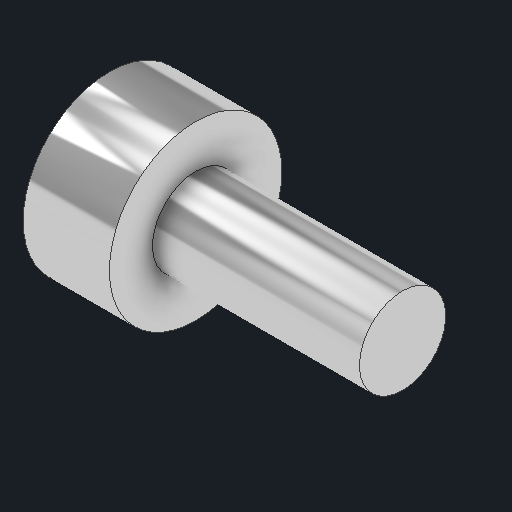
# Autodesk Inventor part: c8n_lock_screw
Saved by Autodesk Inventor 2027.1 (Build 311270010, 270A)
## iProperties
Created: 2026-11-04
Part Number: c8n_lock_screw
Material: Generic
Description: Primary mirror lock screw (x3)
Document SubType Name: Modeling
Designer: Claude (from photos)
Density: 1 g/cm^3
Appearance: Chrome - Polished
Author: alexg
Autodesk Inventor part; units mm, degrees
ref_plane "XZ Plane" through (0, 0, 0) normal (0, 1, 0) x (-1, 0, 0)
ref_plane "Work Plane1" through (-5, 0, 0) normal (1, 0, 0) x (0, 1, 0)
sketch "Head sketch" plane through (-5, 0, 0) normal (1, 0, 0) x (0, 1, 0)
  circle A0 centre (0, 0) radius 5
  constraints: 1 centre point
extrude "Head" add sketch "Head sketch" along normal blind 5
ref_plane "Work Plane2" through (-5, 0, 0) normal (1, 0, 0) x (0, 1, 0)
sketch "Hex socket sketch" plane through (-5, 0, 0) normal (1, 0, 0) x (0, 1, 0)
  line L0 (0, 2.3094) -> (2, 1.1547)
  line L1 (2, 1.1547) -> (2, -1.1547)
  line L2 (2, -1.1547) -> (0, -2.3094)
  line L3 (0, -2.3094) -> (-2, -1.1547)
  line L4 (-2, -1.1547) -> (-2, 1.1547)
  line L5 (-2, 1.1547) -> (0, 2.3094)
  constraints: 12 end point
extrude "Hex socket" cut sketch "Hex socket sketch" along normal blind 3
sketch "M5 lock screw sketch" plane through (0, 0, 0) normal (1, 0, 0) x (0, 1, 0)
  circle A0 centre (0, 0) radius 2.5
  constraints: 1 centre point
extrude "M5 lock screw" add sketch "M5 lock screw sketch" along normal blind 12
body "Solid1"
